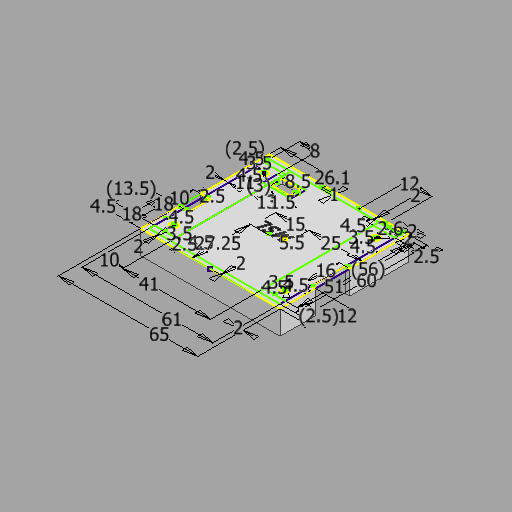
# Autodesk Inventor part: case2
Saved by Autodesk Inventor 2027 (Build 310192000, 192)
## iProperties
Created: 2026-09-07
Part Number: case2
Material: Generic
Document SubType Name: Modeling
Designer: jyjhm
Density: 1 g/cm^3
Appearance: Default
Author: jyjhm
Autodesk Inventor part; units mm, degrees
ref_plane "YZ Plane" through (0, 0, 0) normal (1, 0, 0) x (0, 1, 0)
ref_plane "XZ Plane" through (0, 0, 0) normal (0, 1, 0) x (-1, 0, 0)
ref_plane "XY Plane" through (0, 0, 0) normal (0, 0, 1) x (1, 0, 0)
sketch "Sketch1" plane through (0, 0, 0) normal (0, 1, 0) x (-1, 0, 0)
  line L0 (-24.8206, -28.7293) -> (-24.8206, 26.2707)
  line L1 (-14.8206, -28.7293) -> (-24.8206, -28.7293)
  line L2 (-14.8206, -28.7293) -> (-14.8206, 26.2707)
  line L3 (36.1794, 1.2707) -> (36.1794, -27.2293)
  line L4 (38.1794, 1.2707) -> (36.1794, 1.2707)
  line L5 (38.1794, 11.2707) -> (38.1794, 1.2707)
  line L6 (36.1794, 11.2707) -> (38.1794, 11.2707)
  line L7 (36.1794, 27.2707) -> (36.1794, 11.2707)
  line L8 (26.1794, 27.2707) -> (36.1794, 27.2707)
  line L9 (26.1794, 27.2707) -> (26.1794, -27.2293)
  line L10 (-24.8206, -28.7293) -> (36.1794, -28.7293)
  line L11 (26.1794, 27.2707) -> (26.1794, -28.7293)
  line L12 (26.1794, 24.7707) -> (36.1794, 24.7707)
  line L13 (-14.8206, -28.7293) -> (-14.8206, 26.2707)
  line L14 (-24.8206, 27.2707) -> (-24.8206, -28.7293)
  line L15 (-14.8206, 24.7707) -> (-24.8206, 24.7707)
  line L16 (36.1794, 27.2707) -> (-24.8206, 27.2707)
  line L17 (-24.8206, -28.7293) -> (-6.9788, -28.7293)
  line L18 (-24.8206, -26.2293) -> (-24.8206, -28.7293)
  line L19 (-14.8206, 24.7707) -> (-24.8206, 24.7707)
  line L20 (-24.8206, 24.7707) -> (-24.8206, 27.2707)
  line L21 (-24.8206, 27.2707) -> (-14.8206, 27.2707)
  line L22 (-14.8206, 27.2707) -> (-14.8206, 24.7707)
  line L23 (33.0212, -26.2293) -> (36.1794, -26.2293)
  line L24 (36.1794, -26.2293) -> (36.1794, -28.7293)
  line L25 (36.1794, -28.7293) -> (33.0212, -28.7293)
  line L26 (36.1794, 24.7707) -> (26.1794, 24.7707)
  line L27 (26.1794, 24.7707) -> (26.1794, 27.2707)
  line L28 (26.1794, 27.2707) -> (36.1794, 27.2707)
  line L29 (36.1794, 27.2707) -> (36.1794, 24.7707)
  circle A0 centre (-20.3206, 20.2707) radius 1.75
  circle A1 centre (-20.3206, -21.7293) radius 1.75
  circle A2 centre (31.6794, 20.2707) radius 1.75
  circle A3 centre (31.6794, -21.7293) radius 1.75
  line L30 (36.1794, 27.2707) -> (36.1794, 11.2707)
  line L31 (38.1794, 29.2707) -> (-26.8206, 29.2707)
  line L32 (-26.8206, 29.2707) -> (-26.8206, -30.7293)
  line L33 (-26.8206, -30.7293) -> (38.1794, -30.7293)
  line L34 (38.1794, -30.7293) -> (38.1794, 29.2707)
  line L35 (33.0212, -26.2293) -> (26.1794, -26.2293)
  line L36 (-14.8206, -26.2293) -> (-24.8206, -26.2293)
  line L37 (12.0794, -28.7293) -> (9.0794, -28.7293)
  line L38 (9.0794, -28.7293) -> (9.0794, -29.7293)
  line L39 (9.0794, -29.7293) -> (12.0794, -29.7293)
  line L40 (12.0794, -29.7293) -> (12.0794, -28.7293)
  line L41 (-16.8206, -30.7293) -> (-4.8206, -30.7293)
  line L42 (-4.8206, -30.7293) -> (-4.8206, -28.7293)
  line L43 (-4.8206, -28.7293) -> (-16.8206, -28.7293)
  line L44 (-16.8206, -28.7293) -> (-16.8206, -30.7293)
  line L45 (36.1794, 11.2707) -> (36.1794, 1.2707)
  line L46 (-26.8206, -3.2293) -> (-24.8206, -3.2293)
  line L47 (-24.8206, -3.2293) -> (-24.8206, 12.7707)
  line L48 (-24.8206, 12.7707) -> (-26.8206, 12.7707)
  line L49 (-26.8206, 12.7707) -> (-26.8206, -3.2293)
  line L50 (36.1794, 1.2707) -> (33.6794, 1.2707)
  line L51 (33.6794, 1.2707) -> (33.6794, 11.2707)
  line L52 (33.6794, 11.2707) -> (36.1794, 11.2707)
  line L53 (36.1794, 11.2707) -> (36.1794, 1.2707)
  line L54 (15.1794, -24.7293) -> (28.1794, -24.7293)
  line L55 (28.1794, -24.7293) -> (28.1794, -17.7293)
  line L56 (28.1794, -17.7293) -> (15.1794, -17.7293)
  line L57 (15.1794, -17.7293) -> (15.1794, -24.7293)
  line L58 (16.6794, -23.7293) -> (25.1794, -23.7293)
  line L59 (25.1794, -23.7293) -> (25.1794, -18.7293)
  line L60 (25.1794, -18.7293) -> (16.6794, -18.7293)
  line L61 (16.6794, -18.7293) -> (16.6794, -23.7293)
  point P0 (0, 0)
  point P1 (26.1794, -27.2293)
  point P2 (26.1794, -28.7293)
  point P3 (31.1794, 24.7707)
  point P4 (36.1794, 19.2707)
  point P5 (9.0794, -29.2293)
  point P6 (12.0794, -29.2293)
  point P7 (-24.8206, 12.7707)
  point P8 (-26.8206, 12.7707)
  point P9 (-24.8206, -3.2293)
  point P10 (38.1794, 1.2707)
  point P11 (38.1794, 11.2707)
  point P12 (-16.8206, -28.7293)
  point P13 (9.0794, -28.7293)
  point P14 (-4.8206, -30.7293)
  point P15 (37.1794, 11.2707)
  point P16 (34.9294, 11.2707)
  point P17 (-25.8206, 12.7707)
  point P18 (-19.8206, -28.7293)
  point P19 (36.1794, -27.4793)
  point P20 (-4.8206, -29.7293)
  point P21 (-16.8206, -29.7293)
  point P22 (-19.8206, 24.7707)
  point P23 (34.9294, 1.2707)
  point P24 (38.1794, 1.2707)
  point P25 (-25.8206, -3.2293)
  point P26 (25.1794, -21.2293)
  point P27 (15.1794, -21.2293)
  point P28 (16.6794, -21.2293)
  dimension "d22" = 3.5
  dimension "d24" = 3.5
  dimension "d27" = 3.5
  dimension "d29" = 3.5
  dimension "d31" = 2
  dimension "d41" = 1
  dimension "d91" = 2
  dimension "d92" = 2
  dimension "d93" = 2
  dimension "d94" = 60
  dimension "d95" = 56
  dimension "d96" = 51
  dimension "d97" = 2.5
  dimension "d98" = 2.5
  dimension "d99" = 2.5
  dimension "d100" = 2
  dimension "d103" = 65
  dimension "d104" = 61
  dimension "d105" = 41
  dimension "d106" = 10
  dimension "d109" = 8
  dimension "d110" = 26.1
  dimension "d116" = 12
  dimension "d118" = 4.5
  dimension "d120" = 4.5
  dimension "d121" = 4.5
  dimension "d124" = 4.5
  dimension "d125" = 18
  dimension "d126" = 18
  dimension "d127" = 10
  dimension "d128" = 2.5
  dimension "d129" = 4.5
  dimension "d130" = 13.5
  dimension "d131" = 12
  dimension "d136" = 2.5
  dimension "d140" = 4.5
  dimension "d141" = 4.5
  dimension "d142" = 4.5
  dimension "d143" = 4.5
  dimension "d144" = 8.5
  dimension "d145" = 11
  dimension "d146" = 3
  dimension "d147" = 1.5
  dimension "d148" = 13
  dimension "d150" = 16
  constraints: 116 end point, 19 parallel, 17 midpoint, 12 horizontal, 11 perpendicular, 5 point on line, 4 centre point, 4 vertical, 1 collinear, 15 other
  measures "d22" diameter of A0
  measures "d24" diameter of A1
  measures "d27" diameter of A2
  measures "d29" diameter of A3
  measures "d41" distance of L39.end L37.start
  measures "d92" distance between parallel lines of L32 L14
  measures "d93" distance between parallel lines of L34 L3
  measures "d94" distance of L31.end L33.start
  measures "d95" distance of L14.start L14.end
  measures "d96" distance between parallel lines of L15 L36
  measures "d98" distance between parallel lines of L19 L21
  measures "d99" distance between parallel lines of L8 L12
  measures "d100" distance between parallel lines of L31 L28
  measures "d103" distance of L31.start L31.end
  measures "d104" distance of point (36.179, 27.271) L14.start
  measures "d109" distance between parallel lines of L55 L3
  measures "d110" horizontal distance of L39.end L33.end
  measures "d116" distance of point (-4.821, -29.729) point (-16.821, -29.729)
  measures "d118" distance from line of L36 A1.centre
  measures "d120" vertical distance of point (-19.821, 24.771) A0.centre
  measures "d121" distance from line of L26 A2.centre
  measures "d124" distance from line of L35 A3.centre
  measures "d125" distance from line of point (34.929, 11.271) L31
  measures "d126" distance from line of L31 point (37.179, 11.271)
  measures "d127" distance of point (34.929, 11.271) point (34.929, 1.271)
  measures "d129" distance between parallel lines of L31 L26
  measures "d130" distance from line of L51.end L26
  measures "d131" distance between parallel lines of L48 L15
  measures "d136" distance between parallel lines of L45 L51
  measures "d140" distance from line of L3 A3.centre
  measures "d141" distance from line of L0 A1.centre
  measures "d142" distance from line of L14 A0.centre
  measures "d143" distance from line of L30 A2.centre
  measures "d144" distance of L58.start L58.end
  measures "d145" distance between parallel lines of L3 L59
  measures "d146" distance from line of L55 point (25.179, -21.229)
  measures "d147" distance of point (15.179, -21.229) point (16.679, -21.229)
  measures "d148" distance of L55.end L56.end
  measures "d150" distance from line of point (-25.821, -3.229) L48
extrude "Extrusion1" add sketch "Sketch1" against normal blind 2 contours L1 L44 L33 L32 L46 L0 | L0 L36 L2 L1 | L0 L15 L2 L36 | L1 L10 L42 L33 L44 | L46 L32 L48 L0 | L2 L22 L16 L9 L56 L57 L54 L11 L10 | L48 L32 L31 L34 L6 L7 L8 L16 L14 L0 | L15 L0 L14 L16 L22 L2 | L42 L10 L38 L39 L40 L24 L3 L4 L34 L33 | L10 L40 L39 L38 | L4 L45 L6 L5 | L8 L7 L12 L9 | L50 L51 L52 L45 | L3 L23 L35 L9 L54 L55 L56 L12 L7 L52 L51 L50 | L11 L9 L35 L23 L3 L24 L10 | L56 L55 L54 L9 | L9 L54 L57 L56 | A0 | A1 | A2 | A3 | L61 L60 L59 L58
extrude "Extrusion2" cut sketch "Sketch1" against normal blind 2 contours L46 L32 L48 L0 | L10 L40 L39 L38 | L4 L45 L6 L5 | L50 L51 L52 L45 | A0 | A1 | A2 | A3 | L61 L60 L59 L58
extrude "Extrusion6" add sketch "Sketch1" against normal blind 11 contours L1 L44 L33 L32 L46 L0 | L48 L32 L31 L34 L6 L7 L8 L16 L14 L0 | L42 L10 L38 L39 L40 L24 L3 L4 L34 L33
extrude "Extrusion7" add sketch "Sketch1" against normal blind 2 contours L10 L40 L39 L38
sketch "Sketch2" plane through (0, 0, 0) normal (0, 1, 0) x (1, 0, 0)
  line L0 (-38.1794, -1.2707) -> (-33.6794, -1.2707) projected
  line L1 (-33.6794, -1.2707) -> (-33.6794, -11.2707) projected
  line L2 (-33.6794, -11.2707) -> (-38.1794, -11.2707) projected
  line L3 (-38.1794, -11.2707) -> (-38.1794, -29.2707) projected
  line L4 (-38.1794, -29.2707) -> (26.8206, -29.2707) projected
  line L5 (26.8206, -29.2707) -> (26.8206, -12.7707) projected
  line L6 (26.8206, -12.7707) -> (24.8206, -12.7707) projected
  line L7 (24.8206, -12.7707) -> (24.8206, 3.2293) projected
  line L8 (24.8206, 3.2293) -> (26.8206, 3.2293) projected
  line L9 (26.8206, 3.2293) -> (26.8206, 30.7293) projected
  line L10 (26.8206, 30.7293) -> (-38.1794, 30.7293) projected
  line L11 (-38.1794, 30.7293) -> (-38.1794, -1.2707) projected
  circle A0 centre (-31.6794, 21.7293) radius 1.75 projected
  circle A1 centre (20.3206, -20.2707) radius 1.75 projected
  circle A2 centre (-31.6794, -20.2707) radius 1.75 projected
  circle A3 centre (20.3206, 21.7293) radius 1.75 projected
  line L12 (-16.6794, 18.7293) -> (-25.1794, 18.7293) projected
  line L13 (-25.1794, 18.7293) -> (-25.1794, 23.7293) projected
  line L14 (-25.1794, 23.7293) -> (-16.6794, 23.7293) projected
  line L15 (-16.6794, 23.7293) -> (-16.6794, 18.7293) projected
  line L16 (1.7441, -2.125) -> (-13.2559, -1.9164) construction
  line L17 (-13.2559, -1.9164) -> (-13.1794, 3.5836) construction
  line L18 (-13.1794, 3.5836) -> (1.8206, 3.375) construction
  line L19 (1.8206, 3.375) -> (1.7441, -2.125) construction
  line L20 (24.8349, 27.4293) -> (24.8063, 27.4293) construction
  line L21 (24.8063, 27.4293) -> (24.8063, 30.0293) construction
  line L22 (24.8063, 30.0293) -> (24.8349, 30.0293) construction
  line L23 (24.8349, 30.0293) -> (24.8349, 27.4293) construction
  line L24 (1.1907, 3.0505) -> (-0.6054, -2.005)
  line L25 (-0.6054, -2.005) -> (-1.7299, -1.9894)
  line L26 (-1.7299, -1.9894) -> (-1.75, 0.396)
  spline S0 degree 2 poles (-1.75, 0.396) (-1.7517, 0.6239) (-1.7254, 1.1228) (-1.7123, 1.365) knots 0 0 0 1 2 2 2
  line L27 (-1.7123, 1.365) -> (-1.7511, 1.3656)
  spline S1 degree 2 poles (-1.7511, 1.3656) (-1.9144, 1.1255) (-2.2461, 0.6307) (-2.3947, 0.405) knots 0 0 0 1 2 2 2
  line L28 (-2.3947, 0.405) -> (-4.0854, -1.9566)
  line L29 (-4.0854, -1.9566) -> (-5.2099, -1.941)
  line L30 (-5.2099, -1.941) -> (-3.4138, 3.1145)
  line L31 (-3.4138, 3.1145) -> (-2.488, 3.1016)
  line L32 (-2.488, 3.1016) -> (-3.2348, 0.9935)
  spline S2 degree 2 poles (-3.2348, 0.9935) (-3.3255, 0.7476) (-3.576, 0.1645) (-3.846, -0.4281) (-3.956, -0.6641) knots 0 0 0 1 2 3 3 3
  line L33 (-3.956, -0.6641) -> (-3.9269, -0.6645)
  line L34 (-3.9269, -0.6645) -> (-3.0911, 0.5213)
  line L35 (-3.0911, 0.5213) -> (-1.5542, 2.6281)
  line L36 (-1.5542, 2.6281) -> (-0.9725, 2.62)
  line L37 (-0.9725, 2.62) -> (-0.9391, 0.4914)
  line L38 (-0.9391, 0.4914) -> (-0.9558, -0.7058)
  line L39 (-0.9558, -0.7058) -> (-0.9267, -0.7062)
  spline S3 degree 2 poles (-0.9267, -0.7062) (-0.8701, -0.4694) (-0.7164, 0.1247) (-0.558, 0.7091) (-0.4673, 0.955) knots 0 0 0 1 2 3 3 3
  line L40 (-0.4673, 0.955) -> (0.2795, 3.0632)
  line L41 (0.2795, 3.0632) -> (1.1907, 3.0505)
  spline S4 degree 2 poles (-6.1315, 3.2493) (-5.6275, 3.2423) (-4.7894, 2.8476) (-4.5472, 2.4855) knots 0 0 0 1 2 2 2
  line L42 (-4.5472, 2.4855) -> (-5.3761, 1.799)
  spline S5 degree 2 poles (-5.3761, 1.799) (-5.5519, 2.0535) (-6.134, 2.3719) (-6.4636, 2.3764) knots 0 0 0 1 2 2 2
  spline S6 degree 2 poles (-6.4636, 2.3764) (-6.8611, 2.382) (-7.3841, 2.0741) (-7.4799, 1.8088) knots 0 0 0 1 2 2 2
  spline S7 degree 2 poles (-7.4799, 1.8088) (-7.5456, 1.6158) (-7.4276, 1.3863) (-7.1489, 1.208) (-6.9563, 1.1132) knots 0 0 0 1 2 3 3 3
  line L43 (-6.9563, 1.1132) -> (-6.3885, 0.8096)
  spline S8 degree 2 poles (-6.3885, 0.8096) (-6.1718, 0.7047) (-5.8228, 0.3508) (-5.6994, -0.1841) (-5.8306, -0.5556) knots 0 0 0 1 2 3 3 3
  spline S9 degree 2 poles (-5.8306, -0.5556) (-5.9818, -0.9704) (-6.6646, -1.6202) (-7.5958, -1.9951) (-8.1047, -1.988) knots 0 0 0 1 2 3 3 3
  spline S10 degree 2 poles (-8.1047, -1.988) (-8.5555, -1.9817) (-9.2729, -1.6276) (-9.4672, -1.3097) knots 0 0 0 1 2 2 2
  line L44 (-9.4672, -1.3097) -> (-8.7314, -0.6898)
  spline S11 degree 2 poles (-8.7314, -0.6898) (-8.5645, -0.8908) (-8.1217, -1.12) (-7.797, -1.1245) knots 0 0 0 1 2 2 2
  spline S12 degree 2 poles (-7.797, -1.1245) (-7.4674, -1.1291) (-6.9788, -0.8547) (-6.888, -0.5991) knots 0 0 0 1 2 2 2
  spline S13 degree 2 poles (-6.888, -0.5991) (-6.8274, -0.4254) (-6.9647, -0.1859) (-7.258, -0.0122) (-7.4409, 0.0776) knots 0 0 0 1 2 3 3 3
  line L45 (-7.4409, 0.0776) -> (-8.0091, 0.3522)
  spline S14 degree 2 poles (-8.0091, 0.3522) (-8.274, 0.4819) (-8.6033, 0.8549) (-8.6735, 1.3794) (-8.5424, 1.746) knots 0 0 0 1 2 3 3 3
  spline S15 degree 2 poles (-8.5424, 1.746) (-8.3961, 2.1561) (-7.703, 2.8445) (-6.7229, 3.2575) (-6.1315, 3.2493) knots 0 0 0 1 2 3 3 3
  line L46 (-8.9392, 3.1914) -> (-10.7305, -1.8642)
  line L47 (-10.7305, -1.8642) -> (-11.7434, -1.8404)
  line L48 (-11.7434, -1.8404) -> (-10.25, 2.3612)
  line L49 (-10.25, 2.3612) -> (-12.3099, 2.3899)
  line L50 (-12.3099, 2.3899) -> (-12.0121, 3.2341)
  line L51 (-12.0121, 3.2341) -> (-8.9392, 3.1914)
  line L52 (24.8495, 30.013) -> (24.0375, 27.473)
  line L53 (24.0375, 27.473) -> (23.4365, 27.473)
  line L54 (23.4365, 27.473) -> (22.6245, 30.013)
  line L55 (22.6245, 30.013) -> (23.1602, 30.013)
  line L56 (23.1602, 30.013) -> (23.5189, 28.6896)
  spline S16 degree 2 poles (23.5189, 28.6896) (23.577, 28.4909) (23.6837, 28.0619) (23.7419, 27.8607) knots 0 0 0 1 2 2 2
  line L57 (23.7419, 27.8607) -> (23.7564, 27.8607)
  spline S17 degree 2 poles (23.7564, 27.8607) (23.8024, 28.0668) (23.9164, 28.4909) (23.9721, 28.6896) knots 0 0 0 1 2 2 2
  line L58 (23.9721, 28.6896) -> (24.3357, 30.013)
  line L59 (24.3357, 30.013) -> (24.8495, 30.013)
  line L60 (24.3454, 29.361) -> (24.3454, 28.9684)
  line L61 (24.3454, 28.9684) -> (23.1384, 28.9684)
  line L62 (23.1384, 28.9684) -> (23.1384, 29.361)
  line L63 (23.1384, 29.361) -> (24.3454, 29.361)
  spline S18 degree 2 poles (21.626, 30.0614) (21.8829, 30.0614) (22.2707, 29.7633) (22.4864, 29.1695) (22.4864, 28.7308) knots 0 0 0 1 2 3 3 3
  spline S19 degree 2 poles (22.4864, 28.7308) (22.4864, 28.297) (22.2707, 27.7178) (21.8829, 27.4293) (21.626, 27.4293) knots 0 0 0 1 2 3 3 3
  spline S20 degree 2 poles (21.626, 27.4293) (21.3642, 27.4293) (20.9813, 27.7202) (20.7656, 28.297) (20.7656, 28.7308) knots 0 0 0 1 2 3 3 3
  spline S21 degree 2 poles (20.7656, 28.7308) (20.7656, 29.1695) (20.9813, 29.7633) (21.3642, 30.0614) (21.626, 30.0614) knots 0 0 0 1 2 3 3 3
  spline S22 degree 2 poles (21.626, 29.6664) (21.5121, 29.6664) (21.3424, 29.4943) (21.2455, 29.0871) (21.2455, 28.7308) knots 0 0 0 1 2 3 3 3
  spline S23 degree 2 poles (21.2455, 28.7308) (21.2455, 28.3794) (21.3424, 27.9771) (21.5121, 27.8171) (21.626, 27.8171) knots 0 0 0 1 2 3 3 3
  spline S24 degree 2 poles (21.626, 27.8171) (21.7326, 27.8171) (21.9071, 27.9771) (22.0089, 28.3794) (22.0089, 28.7308) knots 0 0 0 1 2 3 3 3
  spline S25 degree 2 poles (22.0089, 28.7308) (22.0089, 29.0871) (21.9071, 29.4943) (21.7326, 29.6664) (21.626, 29.6664) knots 0 0 0 1 2 3 3 3
  line L64 (18.4602, 29.4202) -> (18.804, 29.4202)
  line L65 (18.804, 29.4202) -> (18.804, 30.0191)
  line L66 (18.804, 30.0191) -> (19.4194, 30.0191)
  line L67 (19.4194, 30.0191) -> (19.4194, 29.4202)
  line L68 (19.4194, 29.4202) -> (20.5392, 29.4202)
  line L69 (20.5392, 29.4202) -> (20.5392, 28.9467)
  line L70 (20.5392, 28.9467) -> (19.44, 27.473)
  line L71 (19.44, 27.473) -> (18.804, 27.473)
  line L72 (18.804, 27.473) -> (18.804, 28.9632)
  line L73 (18.804, 28.9632) -> (18.4602, 28.9632)
  line L74 (18.4602, 28.9632) -> (18.4602, 29.4202)
  line L75 (19.4194, 28.9632) -> (19.4194, 28.0987)
  line L76 (19.4194, 28.0987) -> (20.0637, 28.9632)
  line L77 (20.0637, 28.9632) -> (19.4194, 28.9632)
  point P0 (-5.6794, -29.2707)
  point P1 (-5.7559, -2.0207)
  point P2 (24.8206, 30.0293)
  point P3 (24.8349, 28.7293)
  dimension "d162" = 15
  dimension "d163" = 5.5
  dimension "d164" = 25
  dimension "d165" = 27.25
  dimension "d167" = 2.6
  dimension "d169" = 2
  dimension "d170" = 2
  constraints: 4 midpoint, 4 other
  measures "d162" horizontal distance of L18.end L17.end
  measures "d163" vertical distance of L16.start L18.end
  measures "d164" distance from line of L9 L18.end
  measures "d165" distance from line of L4 point (-5.756, -2.021)
  measures "d167" distance of L20.start L22.end
  measures "d169" distance from line of L9 point (24.821, 30.029)
  measures "d170" distance from line of L10 point (24.835, 28.729)
emboss "Emboss1" sketch "Sketch2" operation cut depth 0.6 direction (0, -1, 0) contours L24 L25 L26 S0 L27 S1 L28 L29 L30 L31 L32 S2 L33 L34 L35 L36 L37 L38 L39 S3 L40 L41 | S4 L42 S5 S6 S7 L43 S8 S9 S10 L44 S11 S12 S13 L45 S14 S15 | L46 L47 L48 L49 L50 L51
emboss "Emboss2" sketch "Sketch2" operation cut depth 0.6 direction (0, -1, 0) contours L52 L53 L54 L55 L56 L63 L62 L61 S16 L57 S17 L58 L60 L59 | L63 L60 L61 L58 | L58 L61 L56 L63 | L56 L61 L62 L63 | S18 S19 S20 S21 | L64 L65 L66 L67 L68 L69 L70 L71 L72 L73 L74
body "Solid1"
